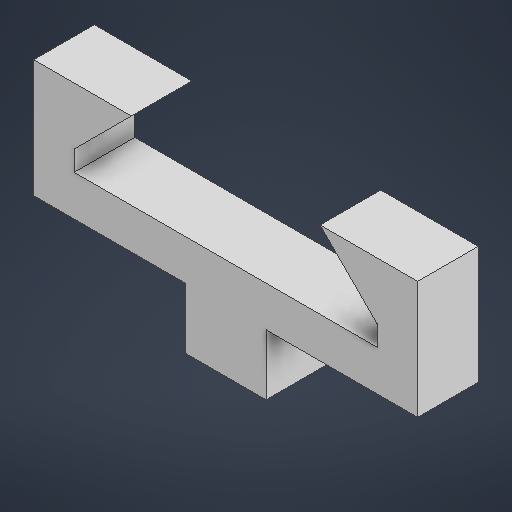
# Autodesk Inventor part: Laser Rx Slot
Saved by Autodesk Inventor 2027.1 (Build 311270010, 270A)
## iProperties
Created: 2026-10-18
Part Number: Laser Rx Slot
Material: Generic
Document SubType Name: Modeling
Designer: Ahmed
Density: 1 g/cm^3
Appearance: Default
Author: Ahmed
Autodesk Inventor part; units mm, degrees
ref_plane "YZ Plane" through (0, 0, 0) normal (1, 0, 0) x (0, 1, 0)
ref_plane "XZ Plane" through (0, 0, 0) normal (0, 1, 0) x (-1, 0, 0)
ref_plane "XY Plane" through (0, 0, 0) normal (0, 0, 1) x (1, 0, 0)
sketch "Sketch1" plane through (0, 0, 0) normal (0, 0, 1) x (1, 0, 0)
  line L0 (-7.5, 0) -> (7.5, 0)
  line L1 (-7.5, 0) -> (-7.5, 1)
  line L2 (7.5, 0) -> (7.5, 1)
  line L3 (-7.5, 1) -> (-4.6716, 3.8284)
  line L4 (-7.5, 1) -> (-3.5, 1) construction
  line L5 (-4.6716, 3.8284) -> (-9.5, 3.8284)
  line L6 (-9.5, 3.8284) -> (-9.5, 0)
  line L7 (-9.5, 0) -> (-7.5, 0)
  line L8 (0, -2.5) -> (0, 2.5)
  line L9 (7.5, 1) -> (4.6716, 3.8284)
  line L10 (4.6716, 3.8284) -> (9.5, 3.8284)
  line L11 (9.5, 3.8284) -> (9.5, 0)
  line L12 (9.5, 0) -> (7.5, 0)
  line L13 (-9.5, 0) -> (9.5, 0)
  line L14 (9.5, 0) -> (9.5, -2)
  line L15 (9.5, -2) -> (-9.5, -2)
  line L16 (-9.5, -2) -> (-9.5, 0)
  line L17 (-2, -2) -> (2, -2)
  line L18 (2, -2) -> (2, -5)
  line L19 (2, -5) -> (-2, -5)
  line L20 (-2, -5) -> (-2, -2)
  point P0 (0, 0)
  point P1 (0, -2)
  dimension "d0" = 15
  dimension "d1" = 1
  dimension "d2" = 4
  dimension "d3" = 45
  dimension "d4" = 2
  dimension "d5" = 5
  dimension "d6" = 2
  dimension "d7" = 2
  dimension "d10" = 4
  dimension "d11" = 3
  constraints: 42 end point, 5 horizontal, 5 perpendicular, 4 midpoint, 4 parallel, 3 symmetric about line, 3 vertical, 1 equal length
  measures "d0" distance of L0.start L0.end
  measures "d1" distance of L0.start L1.end
  measures "d2" distance of L1.end L3.end
  measures "d3" angle of L4 L3
  measures "d4" distance of L6.end L0.start
  measures "d5" distance of L8.start L8.end
  measures "d6" distance of L13.end L14.end
  measures "d7" distance between parallel lines of L14 L2
  measures "d10" distance of L18.end L19.end
  measures "d11" distance of L17.end L18.end
extrude "Extrusion1" add sketch "Sketch1" along normal blind 3
body "Solid1"
